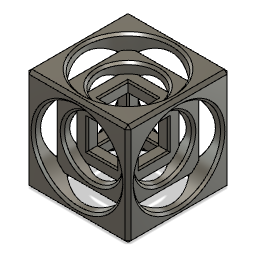
Turner cube (Autodesk Fusion 360 design; units mm, degrees)
Autodesk Fusion 360 part; units mm, degrees
sketch "Sketch1" plane through (0, 0, 0) normal (0, 1, 0) x (1, 0, 0)
  line L0 (-35, 35) -> (35, 35)
  line L1 (35, 35) -> (35, -35)
  line L2 (35, -35) -> (-35, -35)
  line L3 (-35, -35) -> (-35, 35)
  constraint horizontal L0
  constraint vertical L1
  constraint horizontal L2
  constraint vertical L3
extrude "Extrude1" add sketch "Sketch1" along normal blind 70
sketch "Sketch2" plane through (0, 70, 0) normal (0, 1, 0) x (-1, 0, 0)
  line L0 (35, 35) -> (-35, 35)
  line L1 (-35, 35) -> (-35, -35)
  line L2 (-35, -35) -> (35, -35)
  line L3 (35, -35) -> (35, 35)
  circle A0 centre (0, 0) radius 30
  constraint coincident A0.centre origin
sketch "Sketch3" plane through (0, 0, 35) normal (0, 0, 1) x (1, 0, 0)
  line L0 (-35, 0) -> (35, 0)
  line L1 (35, 0) -> (35, 70)
  line L2 (35, 70) -> (-35, 70)
  line L3 (-35, 70) -> (-35, 0)
  circle A0 centre (0, 35) radius 30
sketch "Sketch4" plane through (35, 0, 0) normal (1, 0, 0) x (0, 0, -1)
  line L0 (-35, 0) -> (35, 0)
  line L1 (35, 0) -> (35, 70)
  line L2 (35, 70) -> (-35, 70)
  line L3 (-35, 70) -> (-35, 0)
  circle A0 centre (0, 35) radius 30
extrude "Extrude2" cut sketch "Sketch4" against normal blind 10 contours A0
extrude "Extrude3" cut sketch "Sketch2" against normal blind 10 contours A0
extrude "Extrude4" cut sketch "Sketch3" against normal blind 10 contours A0
sketch "Sketch5" plane through (0, 0, -35) normal (0, 0, -1) x (-1, 0, 0)
  line L0 (-35, 0) -> (35, 0)
  line L1 (35, 0) -> (35, 70)
  line L2 (35, 70) -> (-35, 70)
  line L3 (-35, 70) -> (-35, 0)
  circle A0 centre (0, 35) radius 30
sketch "Sketch6" plane through (-35, 0, 0) normal (-1, 0, 0) x (0, 0, 1)
  line L0 (-35, 0) -> (35, 0)
  line L1 (35, 0) -> (35, 70)
  line L2 (35, 70) -> (-35, 70)
  line L3 (-35, 70) -> (-35, 0)
  circle A0 centre (0, 35) radius 30
sketch "Sketch7" plane through (0, 0, 0) normal (0, -1, 0) x (1, 0, 0)
  line L0 (35, 35) -> (-35, 35)
  line L1 (-35, 35) -> (-35, -35)
  line L2 (-35, -35) -> (35, -35)
  line L3 (35, -35) -> (35, 35)
  circle A0 centre (0, 0) radius 30
  constraint coincident A0.centre origin
extrude "Extrude5" cut sketch "Sketch5" against normal blind 10 contours A0
extrude "Extrude6" cut sketch "Sketch6" against normal blind 10 contours A0
extrude "Extrude7" cut sketch "Sketch7" against normal blind 10 contours A0
sketch "Sketch8" plane through (0, 60, 0) normal (0, 1, 0) x (-1, 0, 0)
  line L0 (25, -16.5831) -> (25, 16.5831)
  arc A0 (25, 16.5831) -> (16.5831, 25) centre (0, 0) ccw
  line L1 (16.5831, 25) -> (-16.5831, 25)
  arc A1 (-16.5831, 25) -> (-25, 16.5831) centre (0, 0) ccw
  line L2 (-25, 16.5831) -> (-25, -16.5831)
  arc A2 (-25, -16.5831) -> (-16.5831, -25) centre (0, 0) ccw
  line L3 (-16.5831, -25) -> (16.5831, -25)
  arc A3 (16.5831, -25) -> (25, -16.5831) centre (0, 0) ccw
  circle A4 centre (0, 0) radius 20
  constraint concentric A0 A4
sketch "Sketch9" plane through (25, 0, 0) normal (1, 0, 0) x (0, 0, -1)
  line L0 (-16.5831, 10) -> (16.5831, 10)
  arc A0 (16.5831, 10) -> (25, 18.4169) centre (0, 35) ccw
  line L1 (25, 18.4169) -> (25, 51.5831)
  arc A1 (25, 51.5831) -> (16.5831, 60) centre (0, 35) ccw
  line L2 (16.5831, 60) -> (-16.5831, 60)
  arc A2 (-16.5831, 60) -> (-25, 51.5831) centre (0, 35) ccw
  line L3 (-25, 51.5831) -> (-25, 18.4169)
  arc A3 (-25, 18.4169) -> (-16.5831, 10) centre (0, 35) ccw
  circle A4 centre (0, 35) radius 20
  constraint concentric A0 A4
sketch "Sketch10" plane through (0, 0, 25) normal (0, 0, 1) x (1, 0, 0)
  line L0 (-16.5831, 10) -> (16.5831, 10)
  arc A0 (16.5831, 10) -> (25, 18.4169) centre (0, 35) ccw
  line L1 (25, 18.4169) -> (25, 51.5831)
  arc A1 (25, 51.5831) -> (16.5831, 60) centre (0, 35) ccw
  line L2 (16.5831, 60) -> (-16.5831, 60)
  arc A2 (-16.5831, 60) -> (-25, 51.5831) centre (0, 35) ccw
  line L3 (-25, 51.5831) -> (-25, 18.4169)
  arc A3 (-25, 18.4169) -> (-16.5831, 10) centre (0, 35) ccw
  circle A4 centre (0, 35) radius 20
  constraint concentric A0 A4
extrude "Extrude8" cut sketch "Sketch9" against normal blind 7 contours A4
extrude "Extrude9" cut sketch "Sketch8" against normal blind 7 contours A4
extrude "Extrude10" cut sketch "Sketch10" against normal blind 7 contours A4
sketch "Sketch11" plane through (-25, 0, 0) normal (-1, 0, 0) x (0, 0, 1)
  line L0 (-16.5831, 10) -> (16.5831, 10)
  arc A0 (16.5831, 10) -> (25, 18.4169) centre (0, 35) ccw
  line L1 (25, 18.4169) -> (25, 51.5831)
  arc A1 (25, 51.5831) -> (16.5831, 60) centre (0, 35) ccw
  line L2 (16.5831, 60) -> (-16.5831, 60)
  arc A2 (-16.5831, 60) -> (-25, 51.5831) centre (0, 35) ccw
  line L3 (-25, 51.5831) -> (-25, 18.4169)
  arc A3 (-25, 18.4169) -> (-16.5831, 10) centre (0, 35) ccw
  circle A4 centre (0, 35) radius 20
  constraint concentric A0 A4
sketch "Sketch12" plane through (0, 0, -25) normal (0, 0, -1) x (-1, 0, 0)
  line L0 (-16.5831, 10) -> (16.5831, 10)
  arc A0 (16.5831, 10) -> (25, 18.4169) centre (0, 35) ccw
  line L1 (25, 18.4169) -> (25, 51.5831)
  arc A1 (25, 51.5831) -> (16.5831, 60) centre (0, 35) ccw
  line L2 (16.5831, 60) -> (-16.5831, 60)
  arc A2 (-16.5831, 60) -> (-25, 51.5831) centre (0, 35) ccw
  line L3 (-25, 51.5831) -> (-25, 18.4169)
  arc A3 (-25, 18.4169) -> (-16.5831, 10) centre (0, 35) ccw
  circle A4 centre (0, 35) radius 20
  constraint concentric A0 A4
sketch "Sketch13" plane through (0, 10, 0) normal (0, -1, 0) x (1, 0, 0)
  line L0 (-25, 16.5831) -> (-25, -16.5831)
  arc A0 (-25, -16.5831) -> (-16.5831, -25) centre (0, 0) ccw
  line L1 (-16.5831, -25) -> (16.5831, -25)
  arc A1 (16.5831, -25) -> (25, -16.5831) centre (0, 0) ccw
  line L2 (25, -16.5831) -> (25, 16.5831)
  arc A2 (25, 16.5831) -> (16.5831, 25) centre (0, 0) ccw
  line L3 (16.5831, 25) -> (-16.5831, 25)
  arc A3 (-16.5831, 25) -> (-25, 16.5831) centre (0, 0) ccw
  circle A4 centre (0, 0) radius 20
  constraint coincident A0.centre A1.centre
extrude "Extrude11" cut sketch "Sketch11" against normal blind 7 contours A4
extrude "Extrude12" cut sketch "Sketch12" against normal blind 7 contours A4
extrude "Extrude13" cut sketch "Sketch13" against normal blind 7 contours A4
sketch "Sketch14" plane through (0, 53, 0) normal (0, 1, 0) x (-1, 0, 0)
  line L0 (-8.7178, -18) -> (8.7178, -18)
  arc A0 (8.7178, -18) -> (18, -8.7178) centre (0, 0) ccw
  line L1 (18, -8.7178) -> (18, 8.7178)
  line L2 (8.7178, 18) -> (-8.7178, 18)
  line L3 (-18, 8.7178) -> (-18, -8.7178)
  line L4 (10, -10) -> (-10, -10)
  line L5 (-10, -10) -> (-10, 10)
  line L6 (-10, 10) -> (10, 10)
  line L7 (10, 10) -> (10, -10)
  arc A1 (18, 8.7178) -> (8.7178, 18) centre (0, 0) ccw
  arc A2 (-8.7178, 18) -> (-18, 8.7178) centre (0, 0) ccw
  arc A3 (-18, -8.7178) -> (-8.7178, -18) centre (0, 0) ccw
  constraint horizontal L4
  constraint vertical L5
  constraint horizontal L6
  constraint vertical L7
sketch "Sketch15" plane through (18, 0, 0) normal (1, 0, 0) x (0, 0, -1)
  line L0 (-8.7178, 17) -> (8.7178, 17)
  arc A0 (8.7178, 17) -> (18, 26.2822) centre (0, 35) ccw
  line L1 (18, 26.2822) -> (18, 43.7178)
  line L2 (8.7178, 53) -> (-8.7178, 53)
  line L3 (-18, 43.7178) -> (-18, 26.2822)
  line L4 (-10, 45) -> (10, 45)
  line L5 (10, 45) -> (10, 25)
  line L6 (10, 25) -> (-10, 25)
  line L7 (-10, 25) -> (-10, 45)
  arc A1 (18, 43.7178) -> (8.7178, 53) centre (0, 35) ccw
  arc A2 (-8.7178, 53) -> (-18, 43.7178) centre (0, 35) ccw
  arc A3 (-18, 26.2822) -> (-8.7178, 17) centre (0, 35) ccw
  constraint horizontal L4
  constraint vertical L5
  constraint horizontal L6
  constraint vertical L7
sketch "Sketch16" plane through (0, 0, 18) normal (0, 0, 1) x (1, 0, 0)
  line L0 (-8.7178, 17) -> (8.7178, 17)
  arc A0 (8.7178, 17) -> (18, 26.2822) centre (0, 35) ccw
  line L1 (18, 26.2822) -> (18, 43.7178)
  line L2 (8.7178, 53) -> (-8.7178, 53)
  line L3 (-18, 43.7178) -> (-18, 26.2822)
  line L4 (-10, 45) -> (10, 45)
  line L5 (10, 45) -> (10, 25)
  line L6 (10, 25) -> (-10, 25)
  line L7 (-10, 25) -> (-10, 45)
  arc A1 (18, 43.7178) -> (8.7178, 53) centre (0, 35) ccw
  arc A2 (-8.7178, 53) -> (-18, 43.7178) centre (0, 35) ccw
  arc A3 (-18, 26.2822) -> (-8.7178, 17) centre (0, 35) ccw
  constraint horizontal L4
  constraint vertical L5
  constraint horizontal L6
  constraint vertical L7
extrude "Extrude14" cut sketch "Sketch14" against normal blind 65 contours L4 L5 L6 L7
extrude "Extrude15" cut sketch "Sketch15" against normal blind 105 contours L4 L5 L6 L7
extrude "Extrude16" cut sketch "Sketch16" against normal blind 115 contours L4 L5 L6 L7
chamfer "Chamfer1" distance 2 angle 45 12 edges at (35, 70, 0) (0, 70, 35) (35, 35, 35) (35, 35, -35) (-35, 35, 35) (0, 0, 35) (35, 0, 0) (-35, 70, 0) (0, 70, -35) (-35, 35, -35) (-35, 0, 0) (0, 0, -35)
chamfer "Chamfer2" distance 1.5 angle 45 6 edges at (27.9698, 45.8485, -35) (27.9698, 70, 10.8485) (35, 45.8485, 27.9698) (-27.9698, 45.8485, 35) (-35, 45.8485, -27.9698) (-27.9698, 0, 10.8485)
chamfer "Chamfer3" distance 1.5 angle 45 6 edges at (18.6465, 60, 7.2323) (25, 42.2323, 18.6465) (-18.6465, 42.2323, 25) (-25, 42.2323, -18.6465) (18.6465, 42.2323, -25) (-18.6465, 10, 7.2323)
chamfer "Chamfer4" distance 1.5 angle 45 12 edges at (0, 60, -25) (-25, 60, 0) (0, 60, 25) (25, 60, 0) (25, 35, -25) (25, 10, 0) (25, 35, 25) (0, 10, -25) (-25, 35, -25) (0, 10, 25) (-25, 35, 25) (-25, 10, 0)
chamfer "Chamfer5" distance 1 angle 45 4 edges at (0, 53, -10) (-10, 53, 0) (0, 53, 10) (10, 53, 0)
chamfer "Chamfer6" distance 1 angle 45 4 edges at (-10, 35, -18) (0, 45, -18) (10, 35, -18) (0, 25, -18)
chamfer "Chamfer7" distance 1 angle 45 4 edges at (-10, 17, 0) (0, 17, -10) (10, 17, 0) (0, 17, 10)
chamfer "Chamfer8" distance 1 angle 45 4 edges at (-10, 35, 18) (0, 25, 18) (10, 35, 18) (0, 45, 18)
chamfer "Chamfer9" distance 1 angle 45 4 edges at (18, 45, 0) (18, 35, 10) (18, 25, 0) (18, 35, -10)
chamfer "Chamfer10" distance 1 angle 45 4 edges at (-18, 45, 0) (-18, 35, -10) (-18, 25, 0) (-18, 35, 10)
chamfer "Chamfer11" distance 1 angle 45 12 edges at (0, 25, 10) (-10, 25, 0) (10, 25, 0) (0, 25, -10) (10, 35, -10) (-10, 35, -10) (-10, 35, 10) (10, 35, 10) (0, 45, 10) (10, 45, 0) (0, 45, -10) (-10, 45, 0)
fillet "Fillet1" radius 1 12 edges at (0, 17, -18) (-18, 17, 0) (18, 17, 0) (0, 17, 18) (18, 35, 18) (0, 53, 18) (-18, 35, 18) (18, 53, 0) (0, 53, -18) (-18, 53, 0) (18, 35, -18) (-18, 35, -18)
